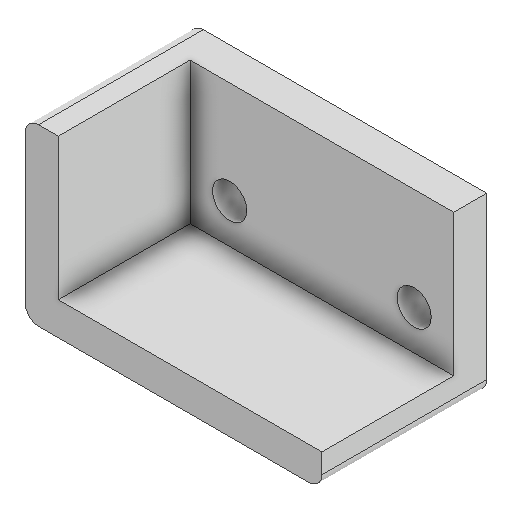
# Autodesk Inventor part: 零件9
Saved by Autodesk Inventor 2027 (Build 310192060, 192F)
## iProperties
Created: 2026-11-23
Part Number: 零件9
Material: 一般
Document SubType Name: Modeling
Designer: 王翊丞
Density: 1 g/cm^3
Appearance: 預設
Author: 王翊丞
Autodesk Inventor part; units mm, degrees
ref_plane "YZ Plane" through (0, 0, 0) normal (1, 0, 0) x (0, 1, 0)
ref_plane "XZ Plane" through (0, 0, 0) normal (0, 1, 0) x (-1, 0, 0)
ref_plane "工作平面1" through (0, 0, 0) normal (0, 0, 1) x (1, 0, 0)
sketch "草圖1" plane through (0, 0, 0) normal (0, 0, 1) x (1, 0, 0)
  circle A0 centre (14, -4) radius 2.6 projected
  circle A1 centre (-14, -4) radius 2.6 projected
  line L0 (-15, -10) -> (15, -10) projected
  line L1 (20, -5) -> (20, 11.5) projected
  line L2 (7, 10) -> (-7, 10) projected
  line L3 (-20, 11.5) -> (-20, -5) projected
  line L4 (20, 11.5) -> (7, 11.5) projected
  line L5 (7, 11.5) -> (7, 10) projected
  line L6 (-7, 10) -> (-7, 11.5) projected
  line L7 (-7, 11.5) -> (-20, 11.5) projected
  circle A2 centre (-14, -4) radius 1.6
  circle A3 centre (14, -4) radius 1.6
  line L8 (-25, 11.5) -> (20, 11.5)
  line L9 (20, 11.5) -> (20, -15)
  line L10 (20, -15) -> (-25, -15)
  line L11 (-25, -15) -> (-25, 11.5)
  arc A4 (15, -10) -> (20, -5) centre (15, -5) ccw projected
  arc A5 (-20, -5) -> (-15, -10) centre (-15, -5) ccw projected
  point P0 (0, 0)
  point P1 (-20, 10)
  point P2 (20, -10)
  dimension "d0" = 3.2
  dimension "d1" = 3.2
  dimension "d2" = 5
  dimension "d3" = 5
  constraints: 8 end point, 2 centre point, 2 coincident, 2 parallel, 1 horizontal, 1 perpendicular
  measures "d0" diameter of A2
  measures "d1" diameter of A3
  measures "d2" distance between parallel lines of L10 L0
  measures "d3" distance between parallel lines of L11 L3
extrude "擠出1" add sketch "草圖1" along normal blind 3 contours A0 | A1 | A5 L3 L7 L6 L2 L5 L4 L1 A4 L0 | L0 A4 L9 L10 L11 L8 L3 A5 | L8 L5 L2 L6
sketch "草圖2" plane through (0, 0, 3) normal (0, 0, 1) x (1, 0, 0)
  line L0 (-25, -15) -> (20, -15) projected
  line L1 (20, -15) -> (20, 11.5) projected
  line L2 (-25, 11.5) -> (-25, -15) projected
  circle A0 centre (-14, -4) radius 1.6 projected
  circle A1 centre (14, -4) radius 1.6 projected
  line L3 (-20, -10) -> (20, -10)
  line L4 (20, -10) -> (20, 11.5)
  line L5 (20, 11.5) -> (-20, 11.5)
  line L6 (-20, 11.5) -> (-20, -10)
  line L7 (-25, -15) -> (20, -15) projected
  line L8 (20, 11.5) -> (-25, 11.5) projected
  point P0 (0, 0)
  point P1 (20, -10)
  point P2 (-20, 11.5)
  dimension "d6" = 5
  dimension "d7" = 5
  constraints: 8 end point, 2 parallel, 1 horizontal, 1 perpendicular
  measures "d6" distance between parallel lines of L7 L3
  measures "d7" distance between parallel lines of L2 L6
extrude "擠出2" add sketch "草圖2" along normal blind 20 contours L2 L8 L6 L3 L1 L0
sketch "草圖3" plane through (0, 0, 0) normal (0, 0, -1) x (-1, 0, 0)
  line L0 (-20, -15) -> (-20, 11.5) projected
  line L1 (25, -15) -> (-20, -15) projected
  line L2 (25, 11.5) -> (25, -15) projected
  line L3 (-20, 11.5) -> (25, 11.5) projected
  circle A0 centre (14, -4) radius 1.6 projected
  circle A1 centre (-14, -4) radius 1.6 projected
  circle A2 centre (-14, -4) radius 2.6
  circle A3 centre (14, -4) radius 2.6
  point P0 (0, 0)
  dimension "d10" = 5.2
  dimension "d11" = 5.2
  constraints: 2 centre point, 2 coincident
  measures "d10" diameter of A2
  measures "d11" diameter of A3
extrude "擠出3" cut sketch "草圖3" against normal up to surface (3 mm away) contours A0 | A1 | A2 | A3
extrude "擠出4" add sketch "草圖3" along normal blind 2 contours L0 L3 L2 L1
fillet "圓角1" radius 2 3 edges at (-25, 11.5, 10.5) (-25, -15, 10.5) (20, -15, 10.5)
